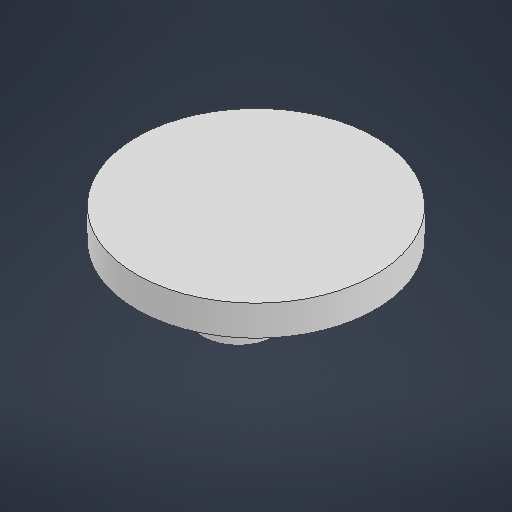
# Autodesk Inventor part: Parachute Bulkhead piston V4
Saved by Autodesk Inventor 2027 (Build 310192060, 192F)
## iProperties
Created: 2026-10-12
Part Number: Parachute Bulkhead piston V4
Material: Generic
Document SubType Name: Modeling
Designer: troop
Density: 1 g/cm^3
Appearance: Default
Author: troop
Autodesk Inventor part; units mm, degrees
ref_plane "XZ Plane" through (0, 0, 0) normal (0, 1, 0) x (-1, 0, 0)
ref_plane "XY Plane" through (0, 0, 0) normal (0, 0, 1) x (1, 0, 0)
sketch "Sketch1" plane through (0, 0, 0) normal (0, 1, 0) x (-1, 0, 0)
  circle A0 centre (0, 0) radius 37.465
  dimension "d0" = 74.93
  constraints: 1 centre point, 1 coincident
  measures "d0" diameter of A0
extrude "Extrusion1" add sketch "Sketch1" along normal blind 9.525
sketch "Sketch8" plane through (0, 0, 0) normal (0, -1, 0) x (1, 0, 0)
  circle A0 centre (0, 5.5563) radius 11.1125
  circle A1 centre (0, 5.5563) radius 14.2875
  point P0 (0, 0)
  dimension "d51" = 5.5563
  dimension "d52" = 22.225
  dimension "d54" = 28.575
  constraints: 2 centre point, 1 concentric, 1 vertical alignment
  measures "d51" distance of A0.centre point (0, 0)
  measures "d52" diameter of A0
  measures "d54" diameter of A1
extrude "Extrusion12" add sketch "Sketch8" along normal blind 17.78 contours A0
ref_plane "Work Plane3" through (10.4775, 0, 0) normal (1, 0, 0) x (0, 1, 0)
sketch "Sketch11" plane through (0, 0, 0) normal (0, 0, 1) x (1, 0, 0)
  circle A0 centre (0, -12.7) radius 3.175
  line L0 (37.465, 0) -> (-37.465, 0) projected
  point P0 (0, 0)
  dimension "d65" = 6.35
  dimension "d66" = 12.7
  constraints: 1 centre point
  measures "d65" diameter of A0
  measures "d66" distance from line of A0.centre L0
extrude "Extrusion14" cut sketch "Sketch11" along normal mid plane 50.8
fillet "Fillet9" radius 2.54 1 edges at (-11.1125, 0, 5.5563)
body "Solid1"
